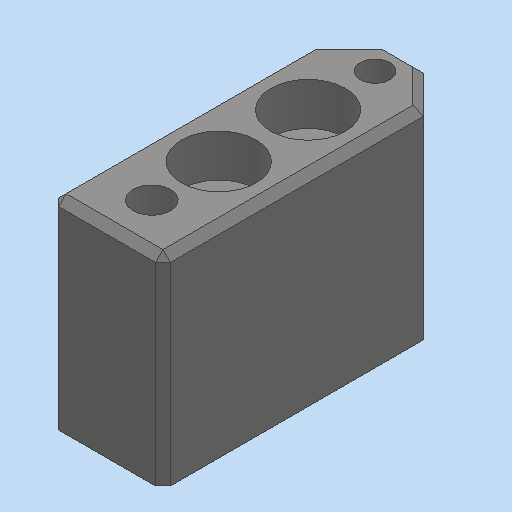
# Autodesk Inventor part: MM0948AN160_G01_105
Saved by Autodesk Inventor 2023.3 (Build 273359000, 359)
## iProperties
RuleStatus: InUse
Part Number: MM0948AN160_G01_105
Material: 1.2379 X155CrVMo12-1
Description: =<RBPARTNOTITLE2>
Document SubType Name: Modeling
Designer: ric7an
Mass: 99.4667 g
Surface Area: 55.6495 cm^2
Volume: 12.6709 cm^3
Density: 7.85 g/cm^3
Appearance: Stahl - rostfrei AnP
Created: 2023-03-23
BeforeDocSave0: file://AnP_Ansicht_ausrichten
RBDOCUMENTTYPE: DRF
RBDOCUMENTVERSION: 00
RBDRAWINGMAINSCALE: 1:1
RBDRAWINGMISSINGSPEC: --
RBDRAWINGVOLUME: --
RBGBEDGESIN1: +0,5
RBGBEDGESIN2: +0,2
RBGBEDGESOUT1: -0,3
RBGBEDGESOUT2: -0,1
RBMATERIAL: =<Material>
RBMATMEETS: --
RBMATNO: =<Part Number>
RBPARTMADEOF: 27 x 40 x 15 (FM)
RBPARTNO: SIEHE MNR
RBPARTNOTITLE1: manufactured part
RBPARTNOTITLE2: Anfertigungsteil
RBPARTSAFETYINDICATOR: --
RBSURFACE: vaccum hardened 61 HRC ± 1
RBSURFACE2: vakuumgehaertet 61 HRC ± 1
RBZEDGESNORM: ISO13715:2002-06
RBZGENDIMCLASS: m
RBZGENDIMNORM: ISO 2768-1:1989-11
RBZGENGEOCLASS: H
RBZGENGEONORM: ISO 2768-2:1989-11
RBZSURFACENORM: ISO13D2:2002-02
RBZTOLERANCENORM: ISO 14405-1:2010-12
AnP_Material: =<Material>
AnP_TemplVers: 20190222
AnP_Kategorie: 1
MaxAbmaße: 27 x 40 x 15 (FM)
AnP_Kommentar_aktuell: =<Comments>
AnP_Material_aktuell: =<Material>
Author: FH/Wi
Keywords: =<RBPARTMADEOF>
Comments: =<RBSURFACE2>
Revision Number: 01
Autodesk Inventor part; units mm, degrees
ref_plane "YZ Plane" through (0, 0, 0) normal (1, 0, 0) x (0, 1, 0)
ref_plane "XZ Plane" through (0, 0, 0) normal (0, 1, 0) x (-1, 0, 0)
ref_plane "XY Plane" through (0, 0, 0) normal (0, 0, 1) x (1, 0, 0)
sketch "Skizze1" plane through (0, 0, 0) normal (0, 0, 1) x (1, 0, 0)
  line L0 (-7.5, 20) -> (7.5, 20)
  line L1 (7.5, 20) -> (7.5, -20)
  line L2 (7.5, -20) -> (-7.5, -20)
  line L3 (-7.5, -20) -> (-7.5, 20)
  line L4 (0, 28) -> (0, -28) projected
  line L5 (-10.5, 0) -> (10.5, 0) projected
  point P0 (0, 0)
  dimension "d0" = 15
  dimension "d1" = 40
  constraints: 8 end point, 2 parallel, 1 horizontal, 1 perpendicular, 2 other
  measures "d0" distance of L0.start L0.end
  measures "d1" distance of L2.end L0.start
extrude "Extrusion1" add sketch "Skizze1" along normal blind 27
sketch "Skizze2" plane through (0, 0, 27) normal (0, 0, 1) x (1, 0, 0)
  line L0 (0, 28) -> (0, -28) projected
  line L1 (-10.5, 0) -> (10.5, 0) projected
  line L2 (-7.5, -20) -> (7.5, -20) projected
  line L3 (7.5, 20) -> (-7.5, 20) projected
  point P0 (0, -5)
  point P1 (0, 7)
  point P2 (0, -14)
  point P3 (0, 16)
  dimension "d36" = 30
  dimension "d37" = 4
  dimension "d42" = 9
  dimension "d43" = 9
  constraints: 4 point on line, 1 other
  measures "d36" distance of point (0, 16) point (0, -14)
  measures "d37" distance from line of point (0, 16) L3
  measures "d42" distance of point (0, 16) point (0, 7)
  measures "d43" distance of point (0, -14) point (0, -5)
hole "Bohrung1" at (0, -5, 27) at (0, 7, 27) direction (0, 0, -1) diameter 5.5 end through all counterbore diameter 10 counterbore depth 5.7 clearance for "Inbusschraube ISO 4762  versenkt" size "M5" standard "ISO"
hole "Bohrung2" at (0, -14, 27) direction (0, 0, -1) diameter 5 end through all
chamfer "Fase3" distance 5 angle 45 2 edges at (-7.5, 20, 13.5) (7.5, 20, 13.5)
chamfer "Fase1" distance 1 angle 45 8 edges at (-7.5, -20, 13.5) (0, -20, 27) (7.5, -20, 13.5) (-7.5, -2.5, 27) (-5, 17.5, 27) (0, 20, 27) (5, 17.5, 27) (7.5, -2.5, 27)
hole "Bohrung3" at (0, 16, 27) direction (0, 0, -1) diameter 4 end through all
